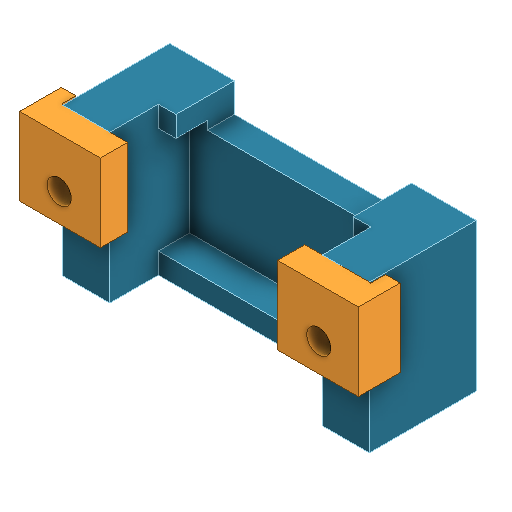
# Autodesk Inventor part: MI-305_Mount_B_Flat_Adhesive
Saved by Autodesk Inventor 2027 (Build 310192060, 192F)
## iProperties
Created: 2026-11-23
Part Number: MI-305_Mount_B_Flat_Adhesive
Material: 一般
Document SubType Name: Modeling
Designer: 王翊丞
Density: 1 g/cm^3
Appearance: 預設
Title: MI-305 B 平放背膠款
Author: 王翊丞
Comments: MI-305 專用。以兩顆 M2 螺絲固定壓片。模型內的底座與壓片是獨立實體。
Autodesk Inventor part; units mm, degrees
sketch "平放承板草圖" plane through (0, 0, 0) normal (0, 0, 1) x (1, 0, 0)
  line L0 (-14.7, -11.95) -> (14.7, -11.95)
  line L1 (14.7, -11.95) -> (14.7, 2.25)
  line L2 (14.7, 2.25) -> (-14.7, 2.25)
  line L3 (-14.7, 2.25) -> (-14.7, -11.95)
  point P0 (0, 0)
  dimension "d0" = 14.7
  dimension "d1" = 11.95
  dimension "d2" = 29.4
  dimension "d3" = 14.2
  constraints: 8 end point, 2 parallel, 1 horizontal, 1 perpendicular, 1 other
  measures "d0" horizontal distance of point (0, 0) L0.start
  measures "d1" vertical distance of point (0, 0) L0.start
  measures "d2" distance of L0.start L0.end
  measures "d3" distance of L0.end L1.end
extrude "平放承板" add sketch "平放承板草圖" along normal blind 2.6
ref_plane "承托面" through (0, 0, 2.6) normal (0, 0, 1) x (1, 0, 0)
sketch "USB 插拔避空草圖" plane through (0, 0, 2.6) normal (0, 0, 1) x (1, 0, 0)
  line L0 (-8.5, -0.55) -> (8.5, -0.55)
  line L1 (8.5, -0.55) -> (8.5, 3.25)
  line L2 (8.5, 3.25) -> (-8.5, 3.25)
  line L3 (-8.5, 3.25) -> (-8.5, -0.55)
  point P0 (0, 0)
  dimension "d7" = 8.5
  dimension "d8" = 0.55
  dimension "d9" = 17
  dimension "d10" = 3.8
  constraints: 8 end point, 2 parallel, 1 horizontal, 1 perpendicular, 1 other
  measures "d7" horizontal distance of point (0, 0) L0.start
  measures "d8" vertical distance of point (0, 0) L0.start
  measures "d9" distance of L0.start L0.end
  measures "d10" distance of L0.end L1.end
extrude "USB 插拔避空" cut sketch "USB 插拔避空草圖" against normal blind 2.6
sketch "左側定位壁草圖" plane through (0, 0, 2.6) normal (0, 0, 1) x (1, 0, 0)
  line L0 (-14.7, -11.95) -> (-10.2, -11.95)
  line L1 (-10.2, -11.95) -> (-10.2, 2.25)
  line L2 (-10.2, 2.25) -> (-14.7, 2.25)
  line L3 (-14.7, 2.25) -> (-14.7, -11.95)
  point P0 (0, 0)
  dimension "d13" = 14.7
  dimension "d14" = 11.95
  dimension "d15" = 4.5
  dimension "d16" = 14.2
  constraints: 8 end point, 2 parallel, 1 horizontal, 1 perpendicular, 1 other
  measures "d13" horizontal distance of point (0, 0) L0.start
  measures "d14" vertical distance of point (0, 0) L0.start
  measures "d15" distance of L0.start L0.end
  measures "d16" distance of L0.end L1.end
extrude "左側定位壁" add sketch "左側定位壁草圖" along normal blind 7.65
sketch "右側定位壁草圖" plane through (0, 0, 2.6) normal (0, 0, 1) x (1, 0, 0)
  line L0 (10.2, -11.95) -> (14.7, -11.95)
  line L1 (14.7, -11.95) -> (14.7, 2.25)
  line L2 (14.7, 2.25) -> (10.2, 2.25)
  line L3 (10.2, 2.25) -> (10.2, -11.95)
  point P0 (0, 0)
  dimension "d19" = 10.2
  dimension "d20" = 11.95
  dimension "d21" = 4.5
  dimension "d22" = 14.2
  constraints: 8 end point, 2 parallel, 1 horizontal, 1 perpendicular, 1 other
  measures "d19" horizontal distance of point (0, 0) L0.start
  measures "d20" vertical distance of point (0, 0) L0.start
  measures "d21" distance of L0.start L0.end
  measures "d22" distance of L0.end L1.end
extrude "右側定位壁" add sketch "右側定位壁草圖" along normal blind 7.65
sketch "弧端定位擋塊草圖" plane through (0, 0, 2.6) normal (0, 0, 1) x (1, 0, 0)
  line L0 (-10.2, -11.95) -> (10.2, -11.95)
  line L1 (10.2, -11.95) -> (10.2, -9.95)
  line L2 (10.2, -9.95) -> (-10.2, -9.95)
  line L3 (-10.2, -9.95) -> (-10.2, -11.95)
  point P0 (0, 0)
  dimension "d25" = 10.2
  dimension "d26" = 11.95
  dimension "d27" = 20.4
  dimension "d28" = 2
  constraints: 8 end point, 2 parallel, 1 horizontal, 1 perpendicular, 1 other
  measures "d25" horizontal distance of point (0, 0) L0.start
  measures "d26" vertical distance of point (0, 0) L0.start
  measures "d27" distance of L0.start L0.end
  measures "d28" distance of L0.end L1.end
extrude "弧端定位擋塊" add sketch "弧端定位擋塊草圖" along normal blind 3
sketch "左肩面擋塊草圖" plane through (0, 0, 2.6) normal (0, 0, 1) x (1, 0, 0)
  line L0 (-10.2, 0.25) -> (-8.5, 0.25)
  line L1 (-8.5, 0.25) -> (-8.5, 2.25)
  line L2 (-8.5, 2.25) -> (-10.2, 2.25)
  line L3 (-10.2, 2.25) -> (-10.2, 0.25)
  point P0 (0, 0)
  dimension "d31" = 10.2
  dimension "d32" = 0.25
  dimension "d33" = 1.7
  dimension "d34" = 2
  constraints: 8 end point, 2 parallel, 1 horizontal, 1 perpendicular, 1 other
  measures "d31" horizontal distance of point (0, 0) L0.start
  measures "d32" vertical distance of point (0, 0) L0.start
  measures "d33" distance of L0.start L0.end
  measures "d34" distance of L0.end L1.end
extrude "左肩面擋塊" add sketch "左肩面擋塊草圖" along normal blind 3
sketch "右肩面擋塊草圖" plane through (0, 0, 2.6) normal (0, 0, 1) x (1, 0, 0)
  line L0 (8.5, 0.25) -> (10.2, 0.25)
  line L1 (10.2, 0.25) -> (10.2, 2.25)
  line L2 (10.2, 2.25) -> (8.5, 2.25)
  line L3 (8.5, 2.25) -> (8.5, 0.25)
  point P0 (0, 0)
  dimension "d37" = 8.5
  dimension "d38" = 0.25
  dimension "d39" = 1.7
  dimension "d40" = 2
  constraints: 8 end point, 2 parallel, 1 horizontal, 1 perpendicular, 1 other
  measures "d37" horizontal distance of point (0, 0) L0.start
  measures "d38" vertical distance of point (0, 0) L0.start
  measures "d39" distance of L0.start L0.end
  measures "d40" distance of L0.end L1.end
extrude "右肩面擋塊" add sketch "右肩面擋塊草圖" along normal blind 3
ref_plane "壓片底面" through (0, 0, 10.25) normal (0, 0, 1) x (1, 0, 0)
sketch "側壁 M2 底孔草圖" plane through (0, 0, 10.25) normal (0, 0, 1) x (1, 0, 0)
  circle A0 centre (-12.45, -2.5) radius 0.85
  circle A1 centre (12.45, -2.5) radius 0.85
  point P0 (0, 0)
  dimension "d44" = 12.45
  dimension "d45" = 2.5
  dimension "d46" = 1.7
  dimension "d47" = 12.45
  dimension "d48" = 2.5
  dimension "d49" = 1.7
  constraints: 2 centre point, 1 other
  measures "d44" horizontal distance of point (0, 0) A0.centre
  measures "d45" vertical distance of point (0, 0) A0.centre
  measures "d46" diameter of A0
  measures "d47" horizontal distance of point (0, 0) A1.centre
  measures "d48" vertical distance of point (0, 0) A1.centre
  measures "d49" diameter of A1
extrude "側壁 M2 底孔" cut sketch "側壁 M2 底孔草圖" against normal blind 4.5
ref_plane "壓片頂面" through (0, 0, 12.85) normal (0, 0, 1) x (1, 0, 0)
ref_plane "壓片定位邊底面" through (0, 0, 8.85) normal (0, 0, 1) x (1, 0, 0)
sketch "左可拆壓片草圖" plane through (0, 0, 10.25) normal (0, 0, 1) x (1, 0, 0)
  line L0 (-16.25, -5.2) -> (-8.5, -5.2)
  line L1 (-8.5, -5.2) -> (-8.5, 2.25)
  line L2 (-8.5, 2.25) -> (-16.25, 2.25)
  line L3 (-16.25, 2.25) -> (-16.25, -5.2)
  point P0 (0, 0)
  dimension "d54" = 16.25
  dimension "d55" = 5.2
  dimension "d56" = 7.75
  dimension "d57" = 7.45
  constraints: 8 end point, 2 parallel, 1 horizontal, 1 perpendicular, 1 other
  measures "d54" horizontal distance of point (0, 0) L0.start
  measures "d55" vertical distance of point (0, 0) L0.start
  measures "d56" distance of L0.start L0.end
  measures "d57" distance of L0.end L1.end
extrude "左可拆壓片" add sketch "左可拆壓片草圖" along normal blind 2.6 separate body
sketch "左壓片防轉定位邊草圖" plane through (0, 0, 8.85) normal (0, 0, 1) x (1, 0, 0)
  line L0 (-16.25, -5.2) -> (-14.85, -5.2)
  line L1 (-14.85, -5.2) -> (-14.85, 2.25)
  line L2 (-14.85, 2.25) -> (-16.25, 2.25)
  line L3 (-16.25, 2.25) -> (-16.25, -5.2)
  point P0 (0, 0)
  dimension "d60" = 16.25
  dimension "d61" = 5.2
  dimension "d62" = 1.4
  dimension "d63" = 7.45
  constraints: 8 end point, 2 parallel, 1 horizontal, 1 perpendicular, 1 other
  measures "d60" horizontal distance of point (0, 0) L0.start
  measures "d61" vertical distance of point (0, 0) L0.start
  measures "d62" distance of L0.start L0.end
  measures "d63" distance of L0.end L1.end
extrude "左壓片防轉定位邊" add sketch "左壓片防轉定位邊草圖" along normal blind 1.4 bodies 2
sketch "左壓片 M2 通孔草圖" plane through (0, 0, 12.85) normal (0, 0, 1) x (1, 0, 0)
  circle A0 centre (-12.45, -2.5) radius 1.15
  point P0 (0, 0)
  dimension "d66" = 12.45
  dimension "d67" = 2.5
  dimension "d68" = 2.3
  constraints: 1 centre point, 1 other
  measures "d66" horizontal distance of point (0, 0) A0.centre
  measures "d67" vertical distance of point (0, 0) A0.centre
  measures "d68" diameter of A0
extrude "左壓片 M2 通孔" cut sketch "左壓片 M2 通孔草圖" against normal blind 2.6 bodies 2
sketch "右可拆壓片草圖" plane through (0, 0, 10.25) normal (0, 0, 1) x (1, 0, 0)
  line L0 (8.5, -5.2) -> (16.25, -5.2)
  line L1 (16.25, -5.2) -> (16.25, 2.25)
  line L2 (16.25, 2.25) -> (8.5, 2.25)
  line L3 (8.5, 2.25) -> (8.5, -5.2)
  point P0 (0, 0)
  dimension "d71" = 8.5
  dimension "d72" = 5.2
  dimension "d73" = 7.75
  dimension "d74" = 7.45
  constraints: 8 end point, 2 parallel, 1 horizontal, 1 perpendicular, 1 other
  measures "d71" horizontal distance of point (0, 0) L0.start
  measures "d72" vertical distance of point (0, 0) L0.start
  measures "d73" distance of L0.start L0.end
  measures "d74" distance of L0.end L1.end
extrude "右可拆壓片" add sketch "右可拆壓片草圖" along normal blind 2.6 separate body
sketch "右壓片防轉定位邊草圖" plane through (0, 0, 8.85) normal (0, 0, 1) x (1, 0, 0)
  line L0 (14.85, -5.2) -> (16.25, -5.2)
  line L1 (16.25, -5.2) -> (16.25, 2.25)
  line L2 (16.25, 2.25) -> (14.85, 2.25)
  line L3 (14.85, 2.25) -> (14.85, -5.2)
  point P0 (0, 0)
  dimension "d77" = 14.85
  dimension "d78" = 5.2
  dimension "d79" = 1.4
  dimension "d80" = 7.45
  constraints: 8 end point, 2 parallel, 1 horizontal, 1 perpendicular, 1 other
  measures "d77" horizontal distance of point (0, 0) L0.start
  measures "d78" vertical distance of point (0, 0) L0.start
  measures "d79" distance of L0.start L0.end
  measures "d80" distance of L0.end L1.end
extrude "右壓片防轉定位邊" add sketch "右壓片防轉定位邊草圖" along normal blind 1.4 bodies 3
sketch "右壓片 M2 通孔草圖" plane through (0, 0, 12.85) normal (0, 0, 1) x (1, 0, 0)
  circle A0 centre (12.45, -2.5) radius 1.15
  point P0 (0, 0)
  dimension "d83" = 12.45
  dimension "d84" = 2.5
  dimension "d85" = 2.3
  constraints: 1 centre point, 1 other
  measures "d83" horizontal distance of point (0, 0) A0.centre
  measures "d84" vertical distance of point (0, 0) A0.centre
  measures "d85" diameter of A0
extrude "右壓片 M2 通孔" cut sketch "右壓片 M2 通孔草圖" against normal blind 2.6 bodies 3
equation "\"d0\" = BaseHalfX"
equation "\"d1\" = -RearY"
equation "\"d2\" = 2 * BaseHalfX"
equation "\"d3\" = FrontY - RearY"
equation "\"d4\" = PlateThickness"
equation "\"d7\" = LipX"
equation "\"d9\" = 2 * LipX"
equation "\"d11\" = PlateThickness"
equation "\"d13\" = OuterX"
equation "\"d14\" = -RearY"
equation "\"d15\" = -InnerX + OuterX"
equation "\"d16\" = FrontY - RearY"
equation "\"d17\" = RailTop - PlateThickness"
equation "\"d19\" = InnerX"
equation "\"d20\" = -RearY"
equation "\"d21\" = OuterX - InnerX"
equation "\"d22\" = FrontY - RearY"
equation "\"d23\" = RailTop - PlateThickness"
equation "\"d25\" = InnerX"
equation "\"d26\" = -RearY"
equation "\"d27\" = 2 * InnerX"
equation "\"d28\" = RearInsideY - RearY"
equation "\"d29\" = StopHeight"
equation "\"d31\" = InnerX"
equation "\"d32\" = FrontInsideY"
equation "\"d33\" = -LipX + InnerX"
equation "\"d34\" = FrontY - FrontInsideY"
equation "\"d35\" = StopHeight"
equation "\"d37\" = LipX"
equation "\"d38\" = FrontInsideY"
equation "\"d39\" = InnerX - LipX"
equation "\"d40\" = FrontY - FrontInsideY"
equation "\"d41\" = StopHeight"
equation "\"d44\" = ScrewX"
equation "\"d45\" = -ScrewY"
equation "\"d46\" = KeeperPilot"
equation "\"d47\" = ScrewX"
equation "\"d48\" = -ScrewY"
equation "\"d49\" = KeeperPilot"
equation "\"d50\" = KeeperPilotDepth"
equation "\"d55\" = -ClipRearY"
equation "\"d57\" = FrontY - ClipRearY"
equation "\"d58\" = KeeperThickness"
equation "\"d61\" = -ClipRearY"
equation "\"d63\" = FrontY - ClipRearY"
equation "\"d66\" = ScrewX"
equation "\"d67\" = -ScrewY"
equation "\"d68\" = KeeperScrewClear"
equation "\"d69\" = KeeperThickness"
equation "\"d71\" = LipX"
equation "\"d72\" = -ClipRearY"
equation "\"d74\" = FrontY - ClipRearY"
equation "\"d75\" = KeeperThickness"
equation "\"d78\" = -ClipRearY"
equation "\"d80\" = FrontY - ClipRearY"
equation "\"d83\" = ScrewX"
equation "\"d84\" = -ScrewY"
equation "\"d85\" = KeeperScrewClear"
equation "\"d86\" = KeeperThickness"
equation "\"HousingWidth\" = 19.8"
equation "\"HousingDepth\" = 9.7"
equation "\"HousingThickness\" = 7.4"
equation "\"FitSide\" = 0.3"
equation "\"FitEnd\" = 0.25"
equation "\"TopClearance\" = 0.25"
equation "\"GripOverlap\" = 1.4"
equation "\"SideWall\" = 4.5"
equation "\"StopWall\" = 2"
equation "\"StopHeight\" = 3"
equation "\"PlateThickness\" = 2.6"
equation "\"KeeperThickness\" = 2.6"
equation "\"KeeperPilot\" = 1.7"
equation "\"KeeperScrewClear\" = 2.3"
equation "\"KeeperPilotDepth\" = 4.5"
equation "\"ShoulderY\" = 0"
equation "\"InnerX\" = 0.5 * HousingWidth + FitSide"
equation "\"OuterX\" = InnerX + SideWall"
equation "\"LipX\" = 0.5 * HousingWidth - GripOverlap"
equation "\"ScrewX\" = InnerX + 0.5 * SideWall"
equation "\"RearY\" = -FitEnd + ShoulderY - HousingDepth - StopWall"
equation "\"RearInsideY\" = RearY + StopWall"
equation "\"FrontInsideY\" = ShoulderY + FitEnd"
equation "\"FrontY\" = FrontInsideY + StopWall"
equation "\"RailTop\" = HousingThickness + PlateThickness + TopClearance"
equation "\"BaseHalfX\" = OuterX"
equation "\"USBOpening\" = 2 * LipX"
equation "\"d6\" = PlateThickness"
equation "\"d43\" = RailTop"
equation "\"d52\" = RailTop + KeeperThickness"
equation "\"ClipRearY\" = -5.2"
equation "\"ScrewY\" = -2.5"
